Autodesk Fusion 360 part; units mm, degrees
(part 8 of 10)
sketch "Thin nut envelope sketch (32)" plane through (0, 0, 20.6) normal (0, 0, 1) x (1, 0, 0) in component "REFERENCE thin METAL channel nut side wall 110"
  line L0 (219.5, 148) -> (222.2, 148)
  line L1 (222.2, 148) -> (222.2, 160)
  line L2 (222.2, 160) -> (219.5, 160)
  line L3 (219.5, 160) -> (219.5, 148)
  dimension "d3288" = 219.5
  dimension "d3289" = 148
  dimension "d3290" = 2.7
  dimension "d3291" = 12
  constraint horizontal L0
  constraint vertical L1
  constraint horizontal L2
  constraint vertical L3
  measures "d3288" horizontal distance of origin L0.start
  measures "d3289" vertical distance of origin L0.start
  measures "d3290" horizontal distance of L0.start L0.end
  measures "d3291" vertical distance of L0.end L1.end
extrude "Thin nut envelope'''''''''''''''''''''''''''''''" add sketch "Thin nut envelope sketch (32)" along normal blind 8.8 separate body makes body 117 in component "REFERENCE thin METAL channel nut side wall 110"
ref_plane "WorkPlane2" through (219.5, 0, 0) normal (1, 0, 0) x (0, 1, 0) in component "REFERENCE thin METAL channel nut side wall 110"
sketch "Thread envelope sketch (32)" plane through (219.5, 0, 0) normal (1, 0, 0) x (0, 0, -1) in component "REFERENCE thin METAL channel nut side wall 110"
  circle A0 centre (-25, 154) radius 2.6
  dimension "d3296" = 25
  dimension "d3297" = 154
  dimension "d3298" = 5.2
  measures "d3296" horizontal distance of origin A0.centre
  measures "d3297" vertical distance of origin A0.centre
  measures "d3298" diameter of A0
extrude "Thread envelope'''''''''''''''''''''''''''''''" cut sketch "Thread envelope sketch (32)" along normal blind 2.7 bodies 117 in component "REFERENCE thin METAL channel nut side wall 110"
ref_plane "WorkPlane4" through (218, 0, 0) normal (1, 0, 0) x (0, 1, 0) in component "METAL flush wall tab 11"
sketch "Side fixing sketch (1) (4)" plane through (218, 0, 0) normal (1, 0, 0) x (0, 0, -1) in component "METAL flush wall tab 11"
  circle A0 centre (-25, 166) radius 2.75
  dimension "d3303" = 25
  dimension "d3304" = 166
  dimension "d3305" = 5.5
  measures "d3303" horizontal distance of origin A0.centre
  measures "d3304" vertical distance of origin A0.centre
  measures "d3305" diameter of A0
extrude "Side fixing (1)'''" cut sketch "Side fixing sketch (1) (4)" against normal blind 3 bodies 115 in component "METAL flush wall tab 11"
ref_plane "WorkPlane1" through (215, 0, 0) normal (1, 0, 0) x (0, 1, 0) in component "REFERENCE side M5x8 wall 111"
sketch "Button head envelope sketch (33)" plane through (215, 0, 0) normal (1, 0, 0) x (0, 0, -1) in component "REFERENCE side M5x8 wall 111"
  circle A0 centre (-25, 166) radius 4.75
  dimension "d3310" = 25
  dimension "d3311" = 166
  dimension "d3312" = 9.5
  measures "d3310" horizontal distance of origin A0.centre
  measures "d3311" vertical distance of origin A0.centre
  measures "d3312" diameter of A0
extrude "Button head envelope''''''''''''''''''''''''''''''''" add sketch "Button head envelope sketch (33)" against normal blind 3 separate body makes body 118 in component "REFERENCE side M5x8 wall 111"
ref_plane "WorkPlane2" through (215, 0, 0) normal (1, 0, 0) x (0, 1, 0) in component "REFERENCE side M5x8 wall 111"
sketch "Shank envelope sketch (33)" plane through (215, 0, 0) normal (1, 0, 0) x (0, 0, -1) in component "REFERENCE side M5x8 wall 111"
  circle A0 centre (-25, 166) radius 2.5
  dimension "d3317" = 25
  dimension "d3318" = 166
  dimension "d3319" = 5
  measures "d3317" horizontal distance of origin A0.centre
  measures "d3318" vertical distance of origin A0.centre
  measures "d3319" diameter of A0
extrude "Shank envelope''''''''''''''''''''''''''''''''" add sketch "Shank envelope sketch (33)" along normal blind 8 bodies 118 in component "REFERENCE side M5x8 wall 111"
ref_plane "WorkPlane1" through (0, 0, 20.6) normal (0, 0, 1) x (1, 0, 0) in component "REFERENCE thin METAL channel nut side wall 111"
sketch "Thin nut envelope sketch (33)" plane through (0, 0, 20.6) normal (0, 0, 1) x (1, 0, 0) in component "REFERENCE thin METAL channel nut side wall 111"
  line L0 (219.5, 160) -> (222.2, 160)
  line L1 (222.2, 160) -> (222.2, 172)
  line L2 (222.2, 172) -> (219.5, 172)
  line L3 (219.5, 172) -> (219.5, 160)
  dimension "d3324" = 219.5
  dimension "d3325" = 160
  dimension "d3326" = 2.7
  dimension "d3327" = 12
  constraint horizontal L0
  constraint vertical L1
  constraint horizontal L2
  constraint vertical L3
  measures "d3324" horizontal distance of origin L0.start
  measures "d3325" vertical distance of origin L0.start
  measures "d3326" horizontal distance of L0.start L0.end
  measures "d3327" vertical distance of L0.end L1.end
extrude "Thin nut envelope''''''''''''''''''''''''''''''''" add sketch "Thin nut envelope sketch (33)" along normal blind 8.8 separate body makes body 119 in component "REFERENCE thin METAL channel nut side wall 111"
ref_plane "WorkPlane2" through (219.5, 0, 0) normal (1, 0, 0) x (0, 1, 0) in component "REFERENCE thin METAL channel nut side wall 111"
sketch "Thread envelope sketch (33)" plane through (219.5, 0, 0) normal (1, 0, 0) x (0, 0, -1) in component "REFERENCE thin METAL channel nut side wall 111"
  circle A0 centre (-25, 166) radius 2.6
  dimension "d3332" = 25
  dimension "d3333" = 166
  dimension "d3334" = 5.2
  measures "d3332" horizontal distance of origin A0.centre
  measures "d3333" vertical distance of origin A0.centre
  measures "d3334" diameter of A0
extrude "Thread envelope''''''''''''''''''''''''''''''''" cut sketch "Thread envelope sketch (33)" along normal blind 2.7 bodies 119 in component "REFERENCE thin METAL channel nut side wall 111"
ref_plane "WorkPlane5" through (0, 0, 32) normal (0, 0, 1) x (1, 0, 0) in component "METAL flush wall tab 11"
sketch "Wall anchor clearance sketch (4)" plane through (0, 0, 32) normal (0, 0, 1) x (1, 0, 0) in component "METAL flush wall tab 11"
  circle A0 centre (205, 160) radius 3.25
  dimension "d3339" = 205
  dimension "d3340" = 160
  dimension "d3341" = 6.5
  measures "d3339" horizontal distance of origin A0.centre
  measures "d3340" vertical distance of origin A0.centre
  measures "d3341" diameter of A0
extrude "Wall anchor clearance'''" cut sketch "Wall anchor clearance sketch (4)" along normal blind 3 bodies 115 in component "METAL flush wall tab 11"
ref_plane "WorkPlane1" through (0, 0, 29) normal (0, 0, 1) x (1, 0, 0) in component "REFERENCE wall anchor HEAD ONLY 11"
sketch "Anchor head envelope sketch (4)" plane through (0, 0, 29) normal (0, 0, 1) x (1, 0, 0) in component "REFERENCE wall anchor HEAD ONLY 11"
  circle A0 centre (205, 160) radius 6
  dimension "d3346" = 205
  dimension "d3347" = 160
  dimension "d3348" = 12
  measures "d3346" horizontal distance of origin A0.centre
  measures "d3347" vertical distance of origin A0.centre
  measures "d3348" diameter of A0
extrude "Anchor head envelope'''" add sketch "Anchor head envelope sketch (4)" along normal blind 3 separate body makes body 120 in component "REFERENCE wall anchor HEAD ONLY 11"
ref_plane "WorkPlane2" through (0, 0, 32) normal (0, 0, 1) x (1, 0, 0) in component "REFERENCE wall anchor HEAD ONLY 11"
sketch "Clearance shank only - anchor not selected sketch (4)" plane through (0, 0, 32) normal (0, 0, 1) x (1, 0, 0) in component "REFERENCE wall anchor HEAD ONLY 11"
  circle A0 centre (205, 160) radius 3
  dimension "d3353" = 205
  dimension "d3354" = 160
  dimension "d3355" = 6
  measures "d3353" horizontal distance of origin A0.centre
  measures "d3354" vertical distance of origin A0.centre
  measures "d3355" diameter of A0
extrude "Clearance shank only - anchor not selected'''" add sketch "Clearance shank only - anchor not selected sketch (4)" along normal blind 3 bodies 120 in component "REFERENCE wall anchor HEAD ONLY 11"
component "Panel lower left" placed x (1, 0, 0) y (0, 1, 0) z (0, 0, 1) at (0, 0, 0)
component "Panel lower right" placed x (1, 0, 0) y (0, 1, 0) z (0, 0, 1) at (0, 0, 0)
component "Panel upper left" placed x (1, 0, 0) y (0, 1, 0) z (0, 0, 1) at (0, 0, 0)
component "Panel upper right" placed x (1, 0, 0) y (0, 1, 0) z (0, 0, 1) at (0, 0, 0)
component "Vertical rail 0 - measured sloped-slot approximation" placed x (1, 0, 0) y (0, 1, 0) z (0, 0, 1) at (0, 0, 0)
component "Vertical rail 1 - measured sloped-slot approximation" placed x (1, 0, 0) y (0, 1, 0) z (0, 0, 1) at (0, 0, 0)
component "Vertical rail 2 - measured sloped-slot approximation" placed x (1, 0, 0) y (0, 1, 0) z (0, 0, 1) at (0, 0, 0)
component "Horizontal tie 00 - measured sloped-slot approximation" placed x (1, 0, 0) y (0, 1, 0) z (0, 0, 1) at (0, 0, 0)
component "Horizontal tie 10 - measured sloped-slot approximation" placed x (1, 0, 0) y (0, 1, 0) z (0, 0, 1) at (0, 0, 0)
component "Horizontal tie 01 - measured sloped-slot approximation" placed x (1, 0, 0) y (0, 1, 0) z (0, 0, 1) at (0, 0, 0)
component "Horizontal tie 11 - measured sloped-slot approximation" placed x (1, 0, 0) y (0, 1, 0) z (0, 0, 1) at (0, 0, 0)
component "METAL cap 00" placed x (1, 0, 0) y (0, 1, 0) z (0, 0, 1) at (0, 0, 0)
component "PRINT registration seat 00" placed x (1, 0, 0) y (0, 1, 0) z (0, 0, 1) at (0, 0, 0)
component "METAL stepped compression spacer 00" placed x (1, 0, 0) y (0, 1, 0) z (0, 0, 1) at (0, 0, 0)
component "REFERENCE front M5x25 00" placed x (1, 0, 0) y (0, 1, 0) z (0, 0, 1) at (0, 0, 0)
component "REFERENCE thin METAL channel nut front 00" placed x (1, 0, 0) y (0, 1, 0) z (0, 0, 1) at (0, 0, 0)
component "METAL cap 01" placed x (1, 0, 0) y (0, 1, 0) z (0, 0, 1) at (0, 0, 0)
component "PRINT registration seat 01" placed x (1, 0, 0) y (0, 1, 0) z (0, 0, 1) at (0, 0, 0)
component "METAL stepped compression spacer 01" placed x (1, 0, 0) y (0, 1, 0) z (0, 0, 1) at (0, 0, 0)
component "REFERENCE front M5x25 01" placed x (1, 0, 0) y (0, 1, 0) z (0, 0, 1) at (0, 0, 0)
component "REFERENCE thin METAL channel nut front 01" placed x (1, 0, 0) y (0, 1, 0) z (0, 0, 1) at (0, 0, 0)
component "METAL cap 02" placed x (1, 0, 0) y (0, 1, 0) z (0, 0, 1) at (0, 0, 0)
component "PRINT registration seat 02" placed x (1, 0, 0) y (0, 1, 0) z (0, 0, 1) at (0, 0, 0)
component "METAL stepped compression spacer 02" placed x (1, 0, 0) y (0, 1, 0) z (0, 0, 1) at (0, 0, 0)
component "REFERENCE front M5x25 02" placed x (1, 0, 0) y (0, 1, 0) z (0, 0, 1) at (0, 0, 0)
component "REFERENCE thin METAL channel nut front 02" placed x (1, 0, 0) y (0, 1, 0) z (0, 0, 1) at (0, 0, 0)
component "METAL cap 10" placed x (1, 0, 0) y (0, 1, 0) z (0, 0, 1) at (0, 0, 0)
component "PRINT registration seat 10" placed x (1, 0, 0) y (0, 1, 0) z (0, 0, 1) at (0, 0, 0)
component "METAL stepped compression spacer 10" placed x (1, 0, 0) y (0, 1, 0) z (0, 0, 1) at (0, 0, 0)
component "REFERENCE front M5x25 10" placed x (1, 0, 0) y (0, 1, 0) z (0, 0, 1) at (0, 0, 0)
component "REFERENCE thin METAL channel nut front 10" placed x (1, 0, 0) y (0, 1, 0) z (0, 0, 1) at (0, 0, 0)
component "METAL cap 11" placed x (1, 0, 0) y (0, 1, 0) z (0, 0, 1) at (0, 0, 0)
component "PRINT registration seat 11" placed x (1, 0, 0) y (0, 1, 0) z (0, 0, 1) at (0, 0, 0)
component "METAL stepped compression spacer 11" placed x (1, 0, 0) y (0, 1, 0) z (0, 0, 1) at (0, 0, 0)
component "REFERENCE front M5x25 11" placed x (1, 0, 0) y (0, 1, 0) z (0, 0, 1) at (0, 0, 0)
component "REFERENCE thin METAL channel nut front 11" placed x (1, 0, 0) y (0, 1, 0) z (0, 0, 1) at (0, 0, 0)
component "METAL cap 12" placed x (1, 0, 0) y (0, 1, 0) z (0, 0, 1) at (0, 0, 0)
component "PRINT registration seat 12" placed x (1, 0, 0) y (0, 1, 0) z (0, 0, 1) at (0, 0, 0)
component "METAL stepped compression spacer 12" placed x (1, 0, 0) y (0, 1, 0) z (0, 0, 1) at (0, 0, 0)
component "REFERENCE front M5x25 12" placed x (1, 0, 0) y (0, 1, 0) z (0, 0, 1) at (0, 0, 0)
component "REFERENCE thin METAL channel nut front 12" placed x (1, 0, 0) y (0, 1, 0) z (0, 0, 1) at (0, 0, 0)
component "METAL cap 20" placed x (1, 0, 0) y (0, 1, 0) z (0, 0, 1) at (0, 0, 0)
component "PRINT registration seat 20" placed x (1, 0, 0) y (0, 1, 0) z (0, 0, 1) at (0, 0, 0)
component "METAL stepped compression spacer 20" placed x (1, 0, 0) y (0, 1, 0) z (0, 0, 1) at (0, 0, 0)
component "REFERENCE front M5x25 20" placed x (1, 0, 0) y (0, 1, 0) z (0, 0, 1) at (0, 0, 0)
component "REFERENCE thin METAL channel nut front 20" placed x (1, 0, 0) y (0, 1, 0) z (0, 0, 1) at (0, 0, 0)
component "METAL cap 21" placed x (1, 0, 0) y (0, 1, 0) z (0, 0, 1) at (0, 0, 0)
component "PRINT registration seat 21" placed x (1, 0, 0) y (0, 1, 0) z (0, 0, 1) at (0, 0, 0)
component "METAL stepped compression spacer 21" placed x (1, 0, 0) y (0, 1, 0) z (0, 0, 1) at (0, 0, 0)
component "REFERENCE front M5x25 21" placed x (1, 0, 0) y (0, 1, 0) z (0, 0, 1) at (0, 0, 0)
component "REFERENCE thin METAL channel nut front 21" placed x (1, 0, 0) y (0, 1, 0) z (0, 0, 1) at (0, 0, 0)
component "METAL cap 22" placed x (1, 0, 0) y (0, 1, 0) z (0, 0, 1) at (0, 0, 0)
component "PRINT registration seat 22" placed x (1, 0, 0) y (0, 1, 0) z (0, 0, 1) at (0, 0, 0)
component "METAL stepped compression spacer 22" placed x (1, 0, 0) y (0, 1, 0) z (0, 0, 1) at (0, 0, 0)
component "REFERENCE front M5x25 22" placed x (1, 0, 0) y (0, 1, 0) z (0, 0, 1) at (0, 0, 0)
component "REFERENCE thin METAL channel nut front 22" placed x (1, 0, 0) y (0, 1, 0) z (0, 0, 1) at (0, 0, 0)
component "METAL in-bay corner 00L" placed x (1, 0, 0) y (0, 1, 0) z (0, 0, 1) at (0, 0, 0)
component "REFERENCE side M5x8 00L X" placed x (1, 0, 0) y (0, 1, 0) z (0, 0, 1) at (0, 0, 0)
component "REFERENCE thin METAL channel nut side 00L X" placed x (1, 0, 0) y (0, 1, 0) z (0, 0, 1) at (0, 0, 0)
component "REFERENCE side M5x8 00L Y" placed x (1, 0, 0) y (0, 1, 0) z (0, 0, 1) at (0, 0, 0)
component "REFERENCE thin METAL channel nut side 00L Y" placed x (1, 0, 0) y (0, 1, 0) z (0, 0, 1) at (0, 0, 0)
component "METAL in-bay corner 00R" placed x (1, 0, 0) y (0, 1, 0) z (0, 0, 1) at (0, 0, 0)
component "REFERENCE side M5x8 00R X" placed x (1, 0, 0) y (0, 1, 0) z (0, 0, 1) at (0, 0, 0)
component "REFERENCE thin METAL channel nut side 00R X" placed x (1, 0, 0) y (0, 1, 0) z (0, 0, 1) at (0, 0, 0)
component "REFERENCE side M5x8 00R Y" placed x (1, 0, 0) y (0, 1, 0) z (0, 0, 1) at (0, 0, 0)
component "REFERENCE thin METAL channel nut side 00R Y" placed x (1, 0, 0) y (0, 1, 0) z (0, 0, 1) at (0, 0, 0)
component "METAL in-bay corner 10L" placed x (1, 0, 0) y (0, 1, 0) z (0, 0, 1) at (0, 0, 0)
component "REFERENCE side M5x8 10L X" placed x (1, 0, 0) y (0, 1, 0) z (0, 0, 1) at (0, 0, 0)
component "REFERENCE thin METAL channel nut side 10L X" placed x (1, 0, 0) y (0, 1, 0) z (0, 0, 1) at (0, 0, 0)
component "REFERENCE side M5x8 10L Y" placed x (1, 0, 0) y (0, 1, 0) z (0, 0, 1) at (0, 0, 0)
component "REFERENCE thin METAL channel nut side 10L Y" placed x (1, 0, 0) y (0, 1, 0) z (0, 0, 1) at (0, 0, 0)
component "METAL in-bay corner 10R" placed x (1, 0, 0) y (0, 1, 0) z (0, 0, 1) at (0, 0, 0)
component "REFERENCE side M5x8 10R X" placed x (1, 0, 0) y (0, 1, 0) z (0, 0, 1) at (0, 0, 0)
component "REFERENCE thin METAL channel nut side 10R X" placed x (1, 0, 0) y (0, 1, 0) z (0, 0, 1) at (0, 0, 0)
component "REFERENCE side M5x8 10R Y" placed x (1, 0, 0) y (0, 1, 0) z (0, 0, 1) at (0, 0, 0)
component "REFERENCE thin METAL channel nut side 10R Y" placed x (1, 0, 0) y (0, 1, 0) z (0, 0, 1) at (0, 0, 0)
component "METAL in-bay corner 01L" placed x (1, 0, 0) y (0, 1, 0) z (0, 0, 1) at (0, 0, 0)
component "REFERENCE side M5x8 01L X" placed x (1, 0, 0) y (0, 1, 0) z (0, 0, 1) at (0, 0, 0)
component "REFERENCE thin METAL channel nut side 01L X" placed x (1, 0, 0) y (0, 1, 0) z (0, 0, 1) at (0, 0, 0)
component "REFERENCE side M5x8 01L Y" placed x (1, 0, 0) y (0, 1, 0) z (0, 0, 1) at (0, 0, 0)
component "REFERENCE thin METAL channel nut side 01L Y" placed x (1, 0, 0) y (0, 1, 0) z (0, 0, 1) at (0, 0, 0)
component "METAL in-bay corner 01R" placed x (1, 0, 0) y (0, 1, 0) z (0, 0, 1) at (0, 0, 0)
component "REFERENCE side M5x8 01R X" placed x (1, 0, 0) y (0, 1, 0) z (0, 0, 1) at (0, 0, 0)
component "REFERENCE thin METAL channel nut side 01R X" placed x (1, 0, 0) y (0, 1, 0) z (0, 0, 1) at (0, 0, 0)
component "REFERENCE side M5x8 01R Y" placed x (1, 0, 0) y (0, 1, 0) z (0, 0, 1) at (0, 0, 0)
component "REFERENCE thin METAL channel nut side 01R Y" placed x (1, 0, 0) y (0, 1, 0) z (0, 0, 1) at (0, 0, 0)
component "METAL in-bay corner 11L" placed x (1, 0, 0) y (0, 1, 0) z (0, 0, 1) at (0, 0, 0)
component "REFERENCE side M5x8 11L X" placed x (1, 0, 0) y (0, 1, 0) z (0, 0, 1) at (0, 0, 0)
component "REFERENCE thin METAL channel nut side 11L X" placed x (1, 0, 0) y (0, 1, 0) z (0, 0, 1) at (0, 0, 0)
component "REFERENCE side M5x8 11L Y" placed x (1, 0, 0) y (0, 1, 0) z (0, 0, 1) at (0, 0, 0)
component "REFERENCE thin METAL channel nut side 11L Y" placed x (1, 0, 0) y (0, 1, 0) z (0, 0, 1) at (0, 0, 0)
component "METAL in-bay corner 11R" placed x (1, 0, 0) y (0, 1, 0) z (0, 0, 1) at (0, 0, 0)
component "REFERENCE side M5x8 11R X" placed x (1, 0, 0) y (0, 1, 0) z (0, 0, 1) at (0, 0, 0)
component "REFERENCE thin METAL channel nut side 11R X" placed x (1, 0, 0) y (0, 1, 0) z (0, 0, 1) at (0, 0, 0)
component "REFERENCE side M5x8 11R Y" placed x (1, 0, 0) y (0, 1, 0) z (0, 0, 1) at (0, 0, 0)
component "REFERENCE thin METAL channel nut side 11R Y" placed x (1, 0, 0) y (0, 1, 0) z (0, 0, 1) at (0, 0, 0)
component "METAL flush wall tab 00" placed x (1, 0, 0) y (0, 1, 0) z (0, 0, 1) at (0, 0, 0)
component "REFERENCE side M5x8 wall 000" placed x (1, 0, 0) y (0, 1, 0) z (0, 0, 1) at (0, 0, 0)
component "REFERENCE thin METAL channel nut side wall 000" placed x (1, 0, 0) y (0, 1, 0) z (0, 0, 1) at (0, 0, 0)
component "REFERENCE side M5x8 wall 001" placed x (1, 0, 0) y (0, 1, 0) z (0, 0, 1) at (0, 0, 0)
component "REFERENCE thin METAL channel nut side wall 001" placed x (1, 0, 0) y (0, 1, 0) z (0, 0, 1) at (0, 0, 0)
component "REFERENCE wall anchor HEAD ONLY 00" placed x (1, 0, 0) y (0, 1, 0) z (0, 0, 1) at (0, 0, 0)
component "METAL flush wall tab 01" placed x (1, 0, 0) y (0, 1, 0) z (0, 0, 1) at (0, 0, 0)
component "REFERENCE side M5x8 wall 010" placed x (1, 0, 0) y (0, 1, 0) z (0, 0, 1) at (0, 0, 0)
component "REFERENCE thin METAL channel nut side wall 010" placed x (1, 0, 0) y (0, 1, 0) z (0, 0, 1) at (0, 0, 0)
component "REFERENCE side M5x8 wall 011" placed x (1, 0, 0) y (0, 1, 0) z (0, 0, 1) at (0, 0, 0)
component "REFERENCE thin METAL channel nut side wall 011" placed x (1, 0, 0) y (0, 1, 0) z (0, 0, 1) at (0, 0, 0)
component "REFERENCE wall anchor HEAD ONLY 01" placed x (1, 0, 0) y (0, 1, 0) z (0, 0, 1) at (0, 0, 0)
component "METAL flush wall tab 10" placed x (1, 0, 0) y (0, 1, 0) z (0, 0, 1) at (0, 0, 0)
component "REFERENCE side M5x8 wall 100" placed x (1, 0, 0) y (0, 1, 0) z (0, 0, 1) at (0, 0, 0)
component "REFERENCE thin METAL channel nut side wall 100" placed x (1, 0, 0) y (0, 1, 0) z (0, 0, 1) at (0, 0, 0)
component "REFERENCE side M5x8 wall 101" placed x (1, 0, 0) y (0, 1, 0) z (0, 0, 1) at (0, 0, 0)
component "REFERENCE thin METAL channel nut side wall 101" placed x (1, 0, 0) y (0, 1, 0) z (0, 0, 1) at (0, 0, 0)
component "REFERENCE wall anchor HEAD ONLY 10" placed x (1, 0, 0) y (0, 1, 0) z (0, 0, 1) at (0, 0, 0)
component "METAL flush wall tab 11" placed x (1, 0, 0) y (0, 1, 0) z (0, 0, 1) at (0, 0, 0)
component "REFERENCE side M5x8 wall 110" placed x (1, 0, 0) y (0, 1, 0) z (0, 0, 1) at (0, 0, 0)
component "REFERENCE thin METAL channel nut side wall 110" placed x (1, 0, 0) y (0, 1, 0) z (0, 0, 1) at (0, 0, 0)
component "REFERENCE side M5x8 wall 111" placed x (1, 0, 0) y (0, 1, 0) z (0, 0, 1) at (0, 0, 0)
component "REFERENCE thin METAL channel nut side wall 111" placed x (1, 0, 0) y (0, 1, 0) z (0, 0, 1) at (0, 0, 0)
component "REFERENCE wall anchor HEAD ONLY 11" placed x (1, 0, 0) y (0, 1, 0) z (0, 0, 1) at (0, 0, 0)
equation "columns = 6" comment "Even integer 4..14; each cell is 20 mm"
equation "rows = 6" comment "Even integer 4..14"
equation "pitch = 20 mm" comment "Keep for dense SKADIS compatible lattice"
equation "panelWidth = columns * pitch" comment "Nominal module pitch X"
equation "panelHeight = rows * pitch" comment "Nominal module pitch Y"
equation "seamGap = 0.2 mm" comment "Physical envelope shrinks around fixed lattice"
equation "boardThickness = 5 mm" comment "Fit-test with real hooks"
equation "slotWidth = 5 mm" comment "Minimum throat width"
equation "slotHeight = 15 mm" comment "Minimum throat height"
equation "entryRadius = 0.4 mm" comment "Front slot and perimeter edge rounding"
equation "cornerRadius = 6 mm" comment "Plan-view panel corner rounding"
equation "hookClearance = 10 mm" comment "PROVISIONAL: board rear to front of extrusion"
equation "frameZ = boardThickness + hookClearance" comment "Front extrusion datum"
equation "mountInset = 12 mm" comment "Exterior node inset from outside module edge"
equation "mountBore = 8.4 mm" comment "Clearance around 8 mm metal shoulder"
equation "capDiameter = 18 mm" comment "Visible decorative mounting disk"
equation "capThickness = 5 mm" comment "Metal clamping cap / washer"
equation "seatThickness = 2 mm" comment "Printed rear bearing washer"
equation "screwDiameter = 5 mm" comment "Nominal M5 reference, threads omitted"
equation "screwClearance = 5.5 mm" comment "Cap and spacer bore"
equation "keyWidth = 4 mm" comment "Registration key corridor width"
equation "keyThickness = 2 mm" comment "Rear removable key body"
equation "keyPegDiameter = 3 mm" comment "Rear locating peg"
equation "keySocketDiameter = 3.4 mm" comment "0.2 mm radial starting fit"
equation "keyPegHeight = 0.8 mm" comment "Peg penetration"
equation "keySocketDepth = 1 mm" comment "Blind locating pocket"
equation "profileMouth = 6.28 mm" comment "User measured mouth"
equation "profileCavity = 11 mm" comment "User measured widest cavity"
equation "profileDepth = 6.2 mm" comment "User measured face-to-floor depth"
equation "profileFloor = 5.7 mm" comment "User estimate, lower confidence"
equation "profileLip = 1.5 mm" comment "Unmeasured; tentative comparable catalog value"
equation "profileTaperStart = profileDepth - ( profileCavity - profileFloor ) / 2" comment "Assumed 45-degree inner slopes"
equation "profileBore = 5 mm" comment "Unmeasured central bore, reference only"
equation "nutWidth = 8.8 mm" comment "Provisional low-profile METAL T-nut envelope, not old rectangular carrier"
equation "nutLength = 12 mm" comment "End-loaded anti-rotation metal nut envelope"
equation "nutThickness = 2.7 mm" comment "Thin nut reference; fit/load still unverified"
equation "jointLeg = 18 mm" comment "In-bay angle footprint"
equation "jointThickness = 3 mm" comment "Metal bracket thickness"
equation "jointDepth = 16 mm" comment "Bracket depth within 20 mm rail"
equation "sideScrewLength = 8 mm" comment "M5x8 reference; check against actual bracket and nut"
equation "registerPin = 2 mm" comment "Node-seat locating pins"
equation "registerSocket = 2.4 mm" comment "Starting printed locating clearance"
equation "registerPinHeight = 0.8 mm" comment "Pin into rear socket"
equation "registerSocketDepth = 1 mm" comment "Blind panel socket"
equation "registerOffset = 5 mm" comment "Four pegs at node +/- offset"
equation "wallTabHeight = 24 mm" comment "Tab along extrusion"
equation "wallTabReach = 22 mm" comment "Tab into open bay"
equation "wallAnchorClearance = 6.5 mm" comment "Placeholder wall anchor interface"
equation "wallShim = 0 mm" comment "Only actual leveling shims; no designed rear air gap"
equation "wallDriverDiameter = 12 mm" comment "Clear tool envelope in open bays"
equation "keyDriverDiameter = 5 mm" comment "Short hex-key working-leg envelope"
equation "keyDriverReach = 20 mm" comment "Short hex-key working-leg reach"
equation "llLeft = 1" comment "0 internal / 1 finished; full cell border and inset mounting"
equation "llRight = 0" comment "0 internal / 1 finished; full cell border and inset mounting"
equation "llBottom = 1" comment "0 internal / 1 finished; full cell border and inset mounting"
equation "llTop = 0" comment "0 internal / 1 finished; full cell border and inset mounting"
equation "d57 = abs(( 0 mm ) + seamGap / 2)"
equation "d58 = abs(( 0 mm ) + seamGap / 2)"
equation "d59 = panelWidth - seamGap"
equation "d60 = panelHeight - seamGap"
equation "d61 = boardThickness"
equation "d64 = cornerRadius"
equation "d65 = slotWidth"
equation "d66 = slotHeight - slotWidth"
equation "d68 = pitch / 2"
equation "d69 = abs(( 0 mm ) + pitch / 4 + pitch * ( llLeft + 1 ))"
equation "d70 = abs(( ( 0 mm ) + pitch / 2 + pitch * llBottom ) - ( slotHeight - slotWidth ) / 2)"
equation "d71 = boardThickness"
equation "d73 = columns - llLeft - llRight - 1"
equation "d74 = rows - llBottom - llTop"
equation "d75 = pitch"
equation "d76 = pitch"
equation "d77 = slotWidth"
equation "d78 = slotHeight - slotWidth"
equation "d80 = pitch / 2"
equation "d81 = abs(( 0 mm ) + pitch / 4 + pitch * llLeft)"
equation "d82 = abs(( ( 0 mm ) + 3 * pitch / 2 + pitch * llBottom ) - ( slotHeight - slotWidth ) / 2)"
equation "d83 = boardThickness"
equation "d86 = rows - llBottom - llTop - 2"
equation "d87 = pitch"
equation "d88 = pitch"
equation "d89 = slotWidth"
equation "d90 = slotHeight - slotWidth"
equation "d92 = pitch / 2"
equation "d93 = abs(( 0 mm ) + 3 * pitch / 4 + pitch * llLeft)"
equation "d94 = abs(( ( 0 mm ) + pitch * llBottom ) - ( slotHeight - slotWidth ) / 2)"
equation "d95 = boardThickness"
equation "d97 = columns - llLeft - llRight - 1"
equation "d98 = rows + 1 - llBottom - llTop"
equation "d99 = pitch"
equation "d100 = pitch"
equation "d101 = slotWidth"
equation "d102 = slotHeight - slotWidth"
equation "d104 = pitch / 2"
equation "d105 = abs(( 0 mm ) + panelWidth - pitch / 4 - pitch * llRight)"
equation "d106 = abs(( ( 0 mm ) + pitch + pitch * llBottom ) - ( slotHeight - slotWidth ) / 2)"
equation "d107 = boardThickness"
equation "d110 = rows - 1 - llBottom - llTop"
equation "d111 = pitch"
equation "d112 = pitch"
equation "d113 = abs(( 0 mm ) + mountInset * llLeft)"
equation "d114 = abs(( 0 mm ) + mountInset * llBottom)"
equation "d115 = mountBore"
equation "d116 = boardThickness"
equation "d118 = abs(( 0 mm ) + mountInset * llLeft)"
equation "d119 = abs(( 0 mm ) + panelHeight - mountInset * llTop)"
equation "d120 = mountBore"
equation "d121 = boardThickness"
equation "d123 = abs(( 0 mm ) + panelWidth - mountInset * llRight)"
equation "d124 = abs(( 0 mm ) + mountInset * llBottom)"
equation "d125 = mountBore"
equation "d126 = boardThickness"
equation "d128 = abs(( 0 mm ) + panelWidth - mountInset * llRight)"
equation "d129 = abs(( 0 mm ) + panelHeight - mountInset * llTop)"
equation "d130 = mountBore"
equation "d131 = boardThickness"
equation "d134 = entryRadius"
equation "d135 = boardThickness"
equation "d137 = abs(( 0 mm ) + panelWidth - pitch / 4)"
equation "d138 = abs(( 0 mm ) + panelHeight / 2 + pitch / 2)"
equation "d139 = keySocketDiameter"
equation "d142 = boardThickness"
equation "d144 = abs(( 0 mm ) + panelWidth / 2 + pitch / 2)"
equation "d145 = abs(( 0 mm ) + panelHeight - pitch / 4)"
equation "d146 = keySocketDiameter"
equation "d149 = boardThickness"
equation "d151 = abs(( 0 mm ) + mountInset * llLeft + ( -1 ) * registerOffset)"
equation "d152 = abs(( 0 mm ) + mountInset * llBottom + ( -1 ) * registerOffset)"
equation "d153 = registerSocket"
equation "d154 = -registerSocketDepth"
equation "d156 = boardThickness"
equation "d158 = abs(( 0 mm ) + mountInset * llLeft + ( -1 ) * registerOffset)"
equation "d159 = abs(( 0 mm ) + mountInset * llBottom + ( 1 ) * registerOffset)"
equation "d160 = registerSocket"
equation "d161 = -registerSocketDepth"
equation "d163 = boardThickness"
equation "d165 = abs(( 0 mm ) + mountInset * llLeft + ( 1 ) * registerOffset)"
equation "d166 = abs(( 0 mm ) + mountInset * llBottom + ( -1 ) * registerOffset)"
equation "d167 = registerSocket"
equation "d168 = -registerSocketDepth"
equation "d170 = boardThickness"
equation "d172 = abs(( 0 mm ) + mountInset * llLeft + ( 1 ) * registerOffset)"
equation "d173 = abs(( 0 mm ) + mountInset * llBottom + ( 1 ) * registerOffset)"
equation "d174 = registerSocket"
equation "d175 = -registerSocketDepth"
equation "d177 = boardThickness"
equation "d179 = abs(( 0 mm ) + mountInset * llLeft + ( -1 ) * registerOffset)"
equation "d180 = abs(( 0 mm ) + panelHeight - mountInset * llTop + ( -1 ) * registerOffset)"
equation "d181 = registerSocket"
equation "d182 = -registerSocketDepth"
equation "d184 = boardThickness"
equation "d186 = abs(( 0 mm ) + mountInset * llLeft + ( 1 ) * registerOffset)"
equation "d187 = abs(( 0 mm ) + panelHeight - mountInset * llTop + ( -1 ) * registerOffset)"
equation "d188 = registerSocket"
equation "d189 = -registerSocketDepth"
equation "d191 = boardThickness"
equation "d193 = abs(( 0 mm ) + panelWidth - mountInset * llRight + ( -1 ) * registerOffset)"
equation "d194 = abs(( 0 mm ) + mountInset * llBottom + ( -1 ) * registerOffset)"
equation "d195 = registerSocket"
equation "d196 = -registerSocketDepth"
equation "d198 = boardThickness"
equation "d200 = abs(( 0 mm ) + panelWidth - mountInset * llRight + ( -1 ) * registerOffset)"
equation "d201 = abs(( 0 mm ) + mountInset * llBottom + ( 1 ) * registerOffset)"
equation "d202 = registerSocket"
equation "d203 = -registerSocketDepth"
equation "d205 = boardThickness"
equation "d207 = abs(( 0 mm ) + panelWidth - mountInset * llRight + ( -1 ) * registerOffset)"
equation "d208 = abs(( 0 mm ) + panelHeight - mountInset * llTop + ( -1 ) * registerOffset)"
equation "d209 = registerSocket"
equation "d210 = -registerSocketDepth"
equation "lrLeft = 0" comment "0 internal / 1 finished; full cell border and inset mounting"
equation "lrRight = 1" comment "0 internal / 1 finished; full cell border and inset mounting"
equation "lrBottom = 1" comment "0 internal / 1 finished; full cell border and inset mounting"
equation "lrTop = 0" comment "0 internal / 1 finished; full cell border and inset mounting"
equation "d216 = abs(( panelWidth ) + seamGap / 2)"
equation "d217 = abs(( 0 mm ) + seamGap / 2)"
equation "d218 = panelWidth - seamGap"
equation "d219 = panelHeight - seamGap"
equation "d220 = boardThickness"
equation "d223 = cornerRadius"
equation "d224 = slotWidth"
equation "d225 = slotHeight - slotWidth"
equation "d227 = pitch / 2"
equation "d228 = abs(( panelWidth ) + pitch / 4 + pitch * ( lrLeft + 1 ))"
equation "d229 = abs(( ( 0 mm ) + pitch / 2 + pitch * lrBottom ) - ( slotHeight - slotWidth ) / 2)"
equation "d230 = boardThickness"
equation "d232 = columns - lrLeft - lrRight - 1"
equation "d233 = rows - lrBottom - lrTop"
equation "d234 = pitch"
equation "d235 = pitch"
equation "d236 = slotWidth"
equation "d237 = slotHeight - slotWidth"
equation "d239 = pitch / 2"
equation "d240 = abs(( panelWidth ) + pitch / 4 + pitch * lrLeft)"
equation "d241 = abs(( ( 0 mm ) + 3 * pitch / 2 + pitch * lrBottom ) - ( slotHeight - slotWidth ) / 2)"
equation "d242 = boardThickness"
equation "d245 = rows - lrBottom - lrTop - 2"
equation "d246 = pitch"
equation "d247 = pitch"
equation "d248 = slotWidth"
equation "d249 = slotHeight - slotWidth"
equation "d251 = pitch / 2"
equation "d252 = abs(( panelWidth ) + 3 * pitch / 4 + pitch * lrLeft)"
equation "d253 = abs(( ( 0 mm ) + pitch * lrBottom ) - ( slotHeight - slotWidth ) / 2)"
equation "d254 = boardThickness"
equation "d256 = columns - lrLeft - lrRight - 1"
equation "d257 = rows + 1 - lrBottom - lrTop"
equation "d258 = pitch"
equation "d259 = pitch"
equation "d260 = slotWidth"
equation "d261 = slotHeight - slotWidth"
equation "d263 = pitch / 2"
equation "d264 = abs(( panelWidth ) + panelWidth - pitch / 4 - pitch * lrRight)"
equation "d265 = abs(( ( 0 mm ) + pitch + pitch * lrBottom ) - ( slotHeight - slotWidth ) / 2)"
equation "d266 = boardThickness"
equation "d269 = rows - 1 - lrBottom - lrTop"
equation "d270 = pitch"
equation "d271 = pitch"
equation "d272 = abs(( panelWidth ) + mountInset * lrLeft)"
equation "d273 = abs(( 0 mm ) + mountInset * lrBottom)"
equation "d274 = mountBore"
equation "d275 = boardThickness"
equation "d277 = abs(( panelWidth ) + mountInset * lrLeft)"
equation "d278 = abs(( 0 mm ) + panelHeight - mountInset * lrTop)"
equation "d279 = mountBore"
equation "d280 = boardThickness"
equation "d282 = abs(( panelWidth ) + panelWidth - mountInset * lrRight)"
equation "d283 = abs(( 0 mm ) + mountInset * lrBottom)"
equation "d284 = mountBore"
equation "d285 = boardThickness"
equation "d287 = abs(( panelWidth ) + panelWidth - mountInset * lrRight)"
equation "d288 = abs(( 0 mm ) + panelHeight - mountInset * lrTop)"
equation "d289 = mountBore"
equation "d290 = boardThickness"
equation "d293 = entryRadius"
equation "d294 = boardThickness"
equation "d296 = abs(( panelWidth ) + pitch / 4)"
equation "d297 = abs(( 0 mm ) + panelHeight / 2 + pitch)"
equation "d298 = keySocketDiameter"
equation "d301 = boardThickness"
equation "d303 = abs(( panelWidth ) + panelWidth / 2 + pitch / 2)"
equation "d304 = abs(( 0 mm ) + panelHeight - pitch / 4)"
equation "d305 = keySocketDiameter"
equation "d308 = boardThickness"
equation "d310 = abs(( panelWidth ) + mountInset * lrLeft + ( 1 ) * registerOffset)"
equation "d311 = abs(( 0 mm ) + mountInset * lrBottom + ( -1 ) * registerOffset)"
equation "d312 = registerSocket"
equation "d313 = -registerSocketDepth"
equation "d315 = boardThickness"
equation "d317 = abs(( panelWidth ) + mountInset * lrLeft + ( 1 ) * registerOffset)"
equation "d318 = abs(( 0 mm ) + mountInset * lrBottom + ( 1 ) * registerOffset)"
equation "d319 = registerSocket"
equation "d320 = -registerSocketDepth"
equation "d322 = boardThickness"
equation "d324 = abs(( panelWidth ) + mountInset * lrLeft + ( 1 ) * registerOffset)"
equation "d325 = abs(( 0 mm ) + panelHeight - mountInset * lrTop + ( -1 ) * registerOffset)"
equation "d326 = registerSocket"
equation "d327 = -registerSocketDepth"
equation "d329 = boardThickness"
equation "d331 = abs(( panelWidth ) + panelWidth - mountInset * lrRight + ( -1 ) * registerOffset)"
equation "d332 = abs(( 0 mm ) + mountInset * lrBottom + ( -1 ) * registerOffset)"
equation "d333 = registerSocket"
equation "d334 = -registerSocketDepth"
equation "d336 = boardThickness"
equation "d338 = abs(( panelWidth ) + panelWidth - mountInset * lrRight + ( -1 ) * registerOffset)"
equation "d339 = abs(( 0 mm ) + mountInset * lrBottom + ( 1 ) * registerOffset)"
equation "d340 = registerSocket"
equation "d341 = -registerSocketDepth"
equation "d343 = boardThickness"
equation "d345 = abs(( panelWidth ) + panelWidth - mountInset * lrRight + ( 1 ) * registerOffset)"
equation "d346 = abs(( 0 mm ) + mountInset * lrBottom + ( -1 ) * registerOffset)"
equation "d347 = registerSocket"
equation "d348 = -registerSocketDepth"
equation "d350 = boardThickness"
equation "d352 = abs(( panelWidth ) + panelWidth - mountInset * lrRight + ( 1 ) * registerOffset)"
equation "d353 = abs(( 0 mm ) + mountInset * lrBottom + ( 1 ) * registerOffset)"
equation "d354 = registerSocket"
equation "d355 = -registerSocketDepth"
equation "d357 = boardThickness"
equation "d359 = abs(( panelWidth ) + panelWidth - mountInset * lrRight + ( -1 ) * registerOffset)"
equation "d360 = abs(( 0 mm ) + panelHeight - mountInset * lrTop + ( -1 ) * registerOffset)"
equation "d361 = registerSocket"
equation "d362 = -registerSocketDepth"
equation "d364 = boardThickness"
equation "d366 = abs(( panelWidth ) + panelWidth - mountInset * lrRight + ( 1 ) * registerOffset)"
equation "d367 = abs(( 0 mm ) + panelHeight - mountInset * lrTop + ( -1 ) * registerOffset)"
equation "d368 = registerSocket"
equation "d369 = -registerSocketDepth"
equation "ulLeft = 1" comment "0 internal / 1 finished; full cell border and inset mounting"
equation "ulRight = 0" comment "0 internal / 1 finished; full cell border and inset mounting"
equation "ulBottom = 0" comment "0 internal / 1 finished; full cell border and inset mounting"
equation "ulTop = 1" comment "0 internal / 1 finished; full cell border and inset mounting"
equation "d375 = abs(( 0 mm ) + seamGap / 2)"
equation "d376 = abs(( panelHeight ) + seamGap / 2)"
equation "d377 = panelWidth - seamGap"
equation "d378 = panelHeight - seamGap"
equation "d379 = boardThickness"
equation "d382 = cornerRadius"
equation "d383 = slotWidth"
equation "d384 = slotHeight - slotWidth"
equation "d386 = pitch / 2"
equation "d387 = abs(( 0 mm ) + pitch / 4 + pitch * ( ulLeft + 1 ))"
equation "d388 = abs(( ( panelHeight ) + pitch / 2 + pitch * ulBottom ) - ( slotHeight - slotWidth ) / 2)"
equation "d389 = boardThickness"
equation "d391 = columns - ulLeft - ulRight - 1"
equation "d392 = rows - ulBottom - ulTop"
equation "d393 = pitch"
equation "d394 = pitch"
equation "d395 = slotWidth"
equation "d396 = slotHeight - slotWidth"
equation "d398 = pitch / 2"
equation "d399 = abs(( 0 mm ) + pitch / 4 + pitch * ulLeft)"
equation "d400 = abs(( ( panelHeight ) + 3 * pitch / 2 + pitch * ulBottom ) - ( slotHeight - slotWidth ) / 2)"
equation "d401 = boardThickness"
equation "d404 = rows - ulBottom - ulTop - 2"
equation "d405 = pitch"
equation "d406 = pitch"
equation "d407 = slotWidth"
equation "d408 = slotHeight - slotWidth"
equation "d410 = pitch / 2"
equation "d411 = abs(( 0 mm ) + 3 * pitch / 4 + pitch * ulLeft)"
equation "d412 = abs(( ( panelHeight ) + pitch * ulBottom ) - ( slotHeight - slotWidth ) / 2)"
equation "d413 = boardThickness"
equation "d415 = columns - ulLeft - ulRight - 1"
equation "d416 = rows + 1 - ulBottom - ulTop"
equation "d417 = pitch"
equation "d418 = pitch"
equation "d419 = slotWidth"
equation "d420 = slotHeight - slotWidth"
equation "d422 = pitch / 2"
equation "d423 = abs(( 0 mm ) + panelWidth - pitch / 4 - pitch * ulRight)"
equation "d424 = abs(( ( panelHeight ) + pitch + pitch * ulBottom ) - ( slotHeight - slotWidth ) / 2)"
equation "d425 = boardThickness"
equation "d428 = rows - 1 - ulBottom - ulTop"
equation "d429 = pitch"
equation "d430 = pitch"
equation "d431 = abs(( 0 mm ) + mountInset * ulLeft)"
equation "d432 = abs(( panelHeight ) + mountInset * ulBottom)"
equation "d433 = mountBore"
equation "d434 = boardThickness"
equation "d436 = abs(( 0 mm ) + mountInset * ulLeft)"
equation "d437 = abs(( panelHeight ) + panelHeight - mountInset * ulTop)"
equation "d438 = mountBore"
equation "d439 = boardThickness"
equation "d441 = abs(( 0 mm ) + panelWidth - mountInset * ulRight)"
equation "d442 = abs(( panelHeight ) + mountInset * ulBottom)"
equation "d443 = mountBore"
equation "d444 = boardThickness"
equation "d446 = abs(( 0 mm ) + panelWidth - mountInset * ulRight)"
equation "d447 = abs(( panelHeight ) + panelHeight - mountInset * ulTop)"
equation "d448 = mountBore"
equation "d449 = boardThickness"
equation "d452 = entryRadius"
equation "d453 = boardThickness"
equation "d455 = abs(( 0 mm ) + panelWidth - pitch / 4)"
equation "d456 = abs(( panelHeight ) + panelHeight / 2 + pitch / 2)"
equation "d457 = keySocketDiameter"
equation "d460 = boardThickness"
equation "d462 = abs(( 0 mm ) + panelWidth / 2 + pitch / 2)"
equation "d463 = abs(( panelHeight ) + pitch / 4)"
equation "d464 = keySocketDiameter"
equation "d467 = boardThickness"
equation "d469 = abs(( 0 mm ) + mountInset * ulLeft + ( -1 ) * registerOffset)"
equation "d470 = abs(( panelHeight ) + mountInset * ulBottom + ( 1 ) * registerOffset)"
equation "d471 = registerSocket"
equation "d472 = -registerSocketDepth"
equation "d474 = boardThickness"
equation "d476 = abs(( 0 mm ) + mountInset * ulLeft + ( 1 ) * registerOffset)"
equation "d477 = abs(( panelHeight ) + mountInset * ulBottom + ( 1 ) * registerOffset)"
equation "d478 = registerSocket"
equation "d479 = -registerSocketDepth"
equation "d481 = boardThickness"
equation "d483 = abs(( 0 mm ) + mountInset * ulLeft + ( -1 ) * registerOffset)"
equation "d484 = abs(( panelHeight ) + panelHeight - mountInset * ulTop + ( -1 ) * registerOffset)"
equation "d485 = registerSocket"
equation "d486 = -registerSocketDepth"
equation "d488 = boardThickness"
equation "d490 = abs(( 0 mm ) + mountInset * ulLeft + ( -1 ) * registerOffset)"
equation "d491 = abs(( panelHeight ) + panelHeight - mountInset * ulTop + ( 1 ) * registerOffset)"
equation "d492 = registerSocket"
equation "d493 = -registerSocketDepth"
equation "d495 = boardThickness"
equation "d497 = abs(( 0 mm ) + mountInset * ulLeft + ( 1 ) * registerOffset)"
equation "d498 = abs(( panelHeight ) + panelHeight - mountInset * ulTop + ( -1 ) * registerOffset)"
equation "d499 = registerSocket"
equation "d500 = -registerSocketDepth"
equation "d502 = boardThickness"
equation "d504 = abs(( 0 mm ) + mountInset * ulLeft + ( 1 ) * registerOffset)"
equation "d505 = abs(( panelHeight ) + panelHeight - mountInset * ulTop + ( 1 ) * registerOffset)"
equation "d506 = registerSocket"
equation "d507 = -registerSocketDepth"
equation "d509 = boardThickness"
equation "d511 = abs(( 0 mm ) + panelWidth - mountInset * ulRight + ( -1 ) * registerOffset)"
equation "d512 = abs(( panelHeight ) + mountInset * ulBottom + ( 1 ) * registerOffset)"
equation "d513 = registerSocket"
equation "d514 = -registerSocketDepth"
equation "d516 = boardThickness"
equation "d518 = abs(( 0 mm ) + panelWidth - mountInset * ulRight + ( -1 ) * registerOffset)"
equation "d519 = abs(( panelHeight ) + panelHeight - mountInset * ulTop + ( -1 ) * registerOffset)"
equation "d520 = registerSocket"
equation "d521 = -registerSocketDepth"
equation "d523 = boardThickness"
equation "d525 = abs(( 0 mm ) + panelWidth - mountInset * ulRight + ( -1 ) * registerOffset)"
equation "d526 = abs(( panelHeight ) + panelHeight - mountInset * ulTop + ( 1 ) * registerOffset)"
equation "d527 = registerSocket"
equation "d528 = -registerSocketDepth"
equation "urLeft = 0" comment "0 internal / 1 finished; full cell border and inset mounting"
equation "urRight = 1" comment "0 internal / 1 finished; full cell border and inset mounting"
equation "urBottom = 0" comment "0 internal / 1 finished; full cell border and inset mounting"
equation "urTop = 1" comment "0 internal / 1 finished; full cell border and inset mounting"
equation "d534 = abs(( panelWidth ) + seamGap / 2)"
equation "d535 = abs(( panelHeight ) + seamGap / 2)"
equation "d536 = panelWidth - seamGap"
equation "d537 = panelHeight - seamGap"
equation "d538 = boardThickness"
equation "d541 = cornerRadius"
equation "d542 = slotWidth"
equation "d543 = slotHeight - slotWidth"
equation "d545 = pitch / 2"
equation "d546 = abs(( panelWidth ) + pitch / 4 + pitch * ( urLeft + 1 ))"
equation "d547 = abs(( ( panelHeight ) + pitch / 2 + pitch * urBottom ) - ( slotHeight - slotWidth ) / 2)"
equation "d548 = boardThickness"
equation "d550 = columns - urLeft - urRight - 1"
equation "d551 = rows - urBottom - urTop"
equation "d552 = pitch"
equation "d553 = pitch"
equation "d554 = slotWidth"
equation "d555 = slotHeight - slotWidth"
equation "d557 = pitch / 2"
equation "d558 = abs(( panelWidth ) + pitch / 4 + pitch * urLeft)"
equation "d559 = abs(( ( panelHeight ) + 3 * pitch / 2 + pitch * urBottom ) - ( slotHeight - slotWidth ) / 2)"
equation "d560 = boardThickness"
equation "d563 = rows - urBottom - urTop - 2"
equation "d564 = pitch"
equation "d565 = pitch"
equation "d566 = slotWidth"
equation "d567 = slotHeight - slotWidth"
equation "d569 = pitch / 2"
equation "d570 = abs(( panelWidth ) + 3 * pitch / 4 + pitch * urLeft)"
equation "d571 = abs(( ( panelHeight ) + pitch * urBottom ) - ( slotHeight - slotWidth ) / 2)"
equation "d572 = boardThickness"
equation "d574 = columns - urLeft - urRight - 1"
equation "d575 = rows + 1 - urBottom - urTop"
equation "d576 = pitch"
equation "d577 = pitch"
equation "d578 = slotWidth"
equation "d579 = slotHeight - slotWidth"
equation "d581 = pitch / 2"
equation "d582 = abs(( panelWidth ) + panelWidth - pitch / 4 - pitch * urRight)"
equation "d583 = abs(( ( panelHeight ) + pitch + pitch * urBottom ) - ( slotHeight - slotWidth ) / 2)"
equation "d584 = boardThickness"
equation "d587 = rows - 1 - urBottom - urTop"
equation "d588 = pitch"
equation "d589 = pitch"
equation "d590 = abs(( panelWidth ) + mountInset * urLeft)"
equation "d591 = abs(( panelHeight ) + mountInset * urBottom)"
equation "d592 = mountBore"
equation "d593 = boardThickness"
equation "d595 = abs(( panelWidth ) + mountInset * urLeft)"
equation "d596 = abs(( panelHeight ) + panelHeight - mountInset * urTop)"
equation "d597 = mountBore"
equation "d598 = boardThickness"
equation "d600 = abs(( panelWidth ) + panelWidth - mountInset * urRight)"
equation "d601 = abs(( panelHeight ) + mountInset * urBottom)"
equation "d602 = mountBore"
equation "d603 = boardThickness"
equation "d605 = abs(( panelWidth ) + panelWidth - mountInset * urRight)"
equation "d606 = abs(( panelHeight ) + panelHeight - mountInset * urTop)"
equation "d607 = mountBore"
equation "d608 = boardThickness"
equation "d611 = entryRadius"
equation "d612 = boardThickness"
equation "d614 = abs(( panelWidth ) + pitch / 4)"
equation "d615 = abs(( panelHeight ) + panelHeight / 2 + pitch)"
equation "d616 = keySocketDiameter"
equation "d619 = boardThickness"
equation "d621 = abs(( panelWidth ) + panelWidth / 2 + pitch / 2)"
equation "d622 = abs(( panelHeight ) + pitch / 4)"
equation "d623 = keySocketDiameter"
equation "d626 = boardThickness"
equation "d628 = abs(( panelWidth ) + mountInset * urLeft + ( 1 ) * registerOffset)"
equation "d629 = abs(( panelHeight ) + mountInset * urBottom + ( 1 ) * registerOffset)"
equation "d630 = registerSocket"
equation "d631 = -registerSocketDepth"
equation "d633 = boardThickness"
equation "d635 = abs(( panelWidth ) + mountInset * urLeft + ( 1 ) * registerOffset)"
equation "d636 = abs(( panelHeight ) + panelHeight - mountInset * urTop + ( -1 ) * registerOffset)"
equation "d637 = registerSocket"
equation "d638 = -registerSocketDepth"
equation "d640 = boardThickness"
equation "d642 = abs(( panelWidth ) + mountInset * urLeft + ( 1 ) * registerOffset)"
equation "d643 = abs(( panelHeight ) + panelHeight - mountInset * urTop + ( 1 ) * registerOffset)"
equation "d644 = registerSocket"
equation "d645 = -registerSocketDepth"
equation "d647 = boardThickness"
equation "d649 = abs(( panelWidth ) + panelWidth - mountInset * urRight + ( -1 ) * registerOffset)"
equation "d650 = abs(( panelHeight ) + mountInset * urBottom + ( 1 ) * registerOffset)"
equation "d651 = registerSocket"
equation "d652 = -registerSocketDepth"
equation "d654 = boardThickness"
equation "d656 = abs(( panelWidth ) + panelWidth - mountInset * urRight + ( 1 ) * registerOffset)"
equation "d657 = abs(( panelHeight ) + mountInset * urBottom + ( 1 ) * registerOffset)"
equation "d658 = registerSocket"
equation "d659 = -registerSocketDepth"
equation "d661 = boardThickness"
equation "d663 = abs(( panelWidth ) + panelWidth - mountInset * urRight + ( -1 ) * registerOffset)"
equation "d664 = abs(( panelHeight ) + panelHeight - mountInset * urTop + ( -1 ) * registerOffset)"
equation "d665 = registerSocket"
equation "d666 = -registerSocketDepth"
equation "d668 = boardThickness"
equation "d670 = abs(( panelWidth ) + panelWidth - mountInset * urRight + ( -1 ) * registerOffset)"
equation "d671 = abs(( panelHeight ) + panelHeight - mountInset * urTop + ( 1 ) * registerOffset)"
equation "d672 = registerSocket"
equation "d673 = -registerSocketDepth"
equation "d675 = boardThickness"
equation "d677 = abs(( panelWidth ) + panelWidth - mountInset * urRight + ( 1 ) * registerOffset)"
equation "d678 = abs(( panelHeight ) + panelHeight - mountInset * urTop + ( -1 ) * registerOffset)"
equation "d679 = registerSocket"
equation "d680 = -registerSocketDepth"
equation "d682 = boardThickness"
equation "d684 = abs(( panelWidth ) + panelWidth - mountInset * urRight + ( 1 ) * registerOffset)"
equation "d685 = abs(( panelHeight ) + panelHeight - mountInset * urTop + ( 1 ) * registerOffset)"
equation "d686 = registerSocket"
equation "d687 = -registerSocketDepth"
equation "d699 = ( mountInset - 10 mm ) * 1.0"
equation "d701 = abs(( ( mountInset ) - 10 mm ) * 1)"
equation "d702 = abs(( frameZ ) * -1)"
equation "d703 = abs(( ( mountInset ) + 10 mm ) * 1)"
equation "d704 = abs(( frameZ + 20 mm ) * -1)"
equation "d705 = ( 2 * panelHeight - 2 * mountInset + 20 mm ) * 1.0"
equation "d707 = ( mountInset - 10 mm ) * 1.0"
equation "d709 = abs(( ( mountInset ) + ( -profileMouth / 2 ) ) * 1)"
equation "d710 = abs(( frameZ + ( 0 mm ) ) * -1)"
equation "d711 = abs(( frameZ + ( profileLip ) ) * -1)"
equation "d712 = abs(( ( mountInset ) + ( -profileCavity / 2 ) ) * 1)"
equation "d713 = abs(( frameZ + ( profileTaperStart ) ) * -1)"
equation "d714 = abs(( ( mountInset ) + ( -profileFloor / 2 ) ) * 1)"
equation "d715 = abs(( frameZ + ( profileDepth ) ) * -1)"
equation "d716 = abs(( ( mountInset ) + ( profileFloor / 2 ) ) * 1)"
equation "d717 = abs(( ( mountInset ) + ( profileCavity / 2 ) ) * 1)"
equation "d718 = abs(( ( mountInset ) + ( profileMouth / 2 ) ) * 1)"
equation "d719 = ( 2 * panelHeight - 2 * mountInset + 20 mm ) * 1.0"
equation "d721 = ( mountInset - 10 mm ) * 1.0"
equation "d723 = abs(( ( mountInset ) + 10 mm - ( 0 mm ) ) * 1)"
equation "d724 = abs(( frameZ + 10 mm + ( -profileMouth / 2 ) ) * -1)"
equation "d725 = abs(( ( mountInset ) + 10 mm - ( profileLip ) ) * 1)"
equation "d726 = abs(( frameZ + 10 mm + ( -profileCavity / 2 ) ) * -1)"
equation "d727 = abs(( ( mountInset ) + 10 mm - ( profileTaperStart ) ) * 1)"
equation "d728 = abs(( ( mountInset ) + 10 mm - ( profileDepth ) ) * 1)"
equation "d729 = abs(( frameZ + 10 mm + ( -profileFloor / 2 ) ) * -1)"
equation "d730 = abs(( frameZ + 10 mm + ( profileFloor / 2 ) ) * -1)"
equation "d731 = abs(( frameZ + 10 mm + ( profileCavity / 2 ) ) * -1)"
equation "d732 = abs(( frameZ + 10 mm + ( profileMouth / 2 ) ) * -1)"
equation "d733 = ( 2 * panelHeight - 2 * mountInset + 20 mm ) * 1.0"
equation "d735 = ( mountInset - 10 mm ) * 1.0"
equation "d737 = abs(( ( mountInset ) - ( -profileMouth / 2 ) ) * 1)"